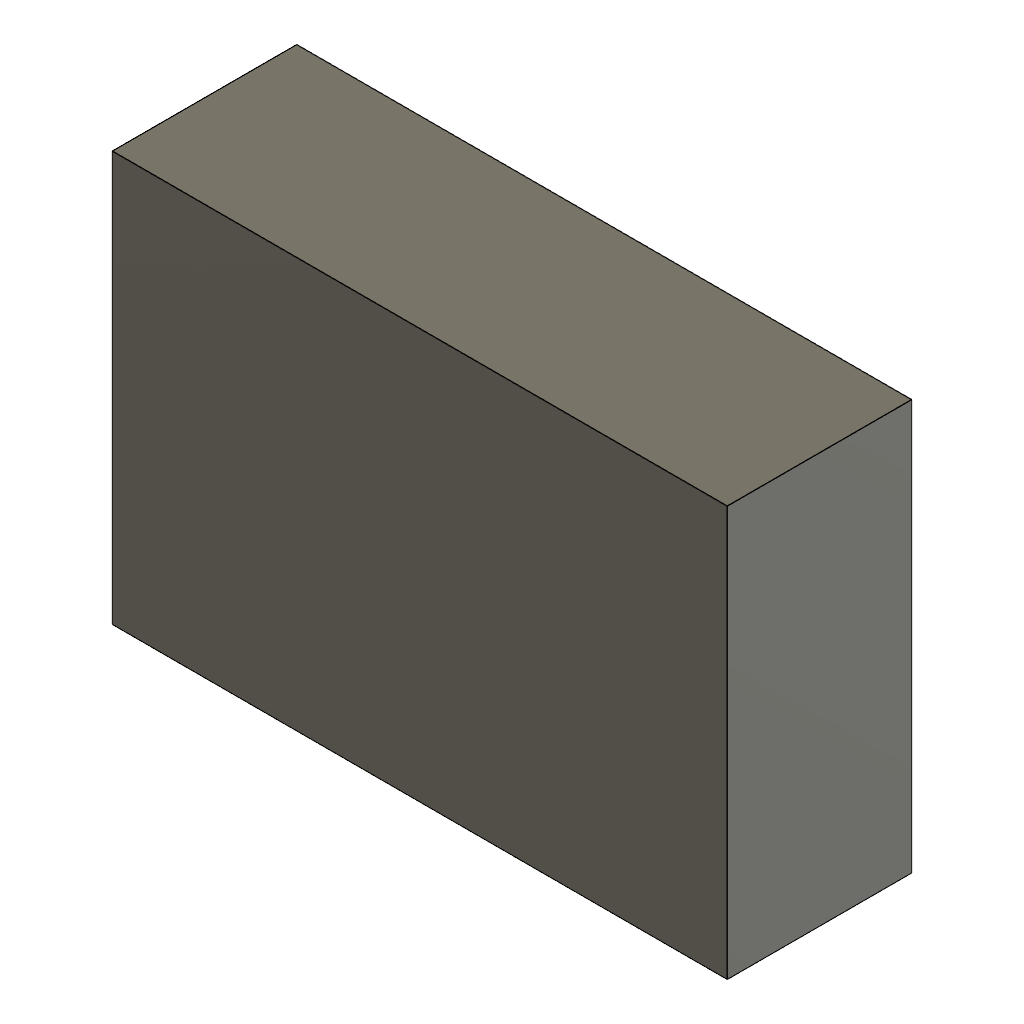
offset_face_press_pull (Autodesk Fusion 360 design; units mm, degrees)
part number: 2026-11-13-14-48-08-482
Autodesk Fusion 360 part; units mm, degrees
sketch "Sketch1" plane through (0, 0, 0) normal (0, 0, 1) x (1, 0, 0)
  line L0 (0, 0) -> (30, 0)
  line L1 (30, 0) -> (30, 20)
  line L2 (30, 20) -> (0, 20)
  line L3 (0, 20) -> (0, 0)
extrude "Extrude1" add sketch "Sketch1" along normal blind 6
move_face "OffsetFaces1" offset 3 1 faces at (10, 13.3333, 6)
